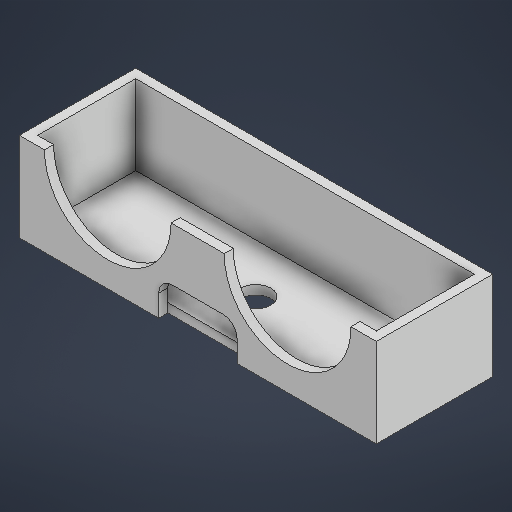
# Autodesk Inventor part: Ultrasonic Sensor Bracket Design
Saved by Autodesk Inventor 2027.1 (Build 311270010, 270A)
## iProperties
Created: 2026-10-28
Part Number: Ultrasonic Sensor Bracket Design
Material: Generic
Document SubType Name: Modeling
Designer: gaelo
Density: 1 g/cm^3
Appearance: Default
Author: gaelo
Autodesk Inventor part; units mm, degrees
ref_plane "YZ Plane" through (0, 0, 0) normal (1, 0, 0) x (0, 1, 0)
ref_plane "XZ Plane" through (0, 0, 0) normal (0, 1, 0) x (-1, 0, 0)
ref_plane "XY Plane" through (0, 0, 0) normal (0, 0, 1) x (1, 0, 0)
sketch "Sketch1" plane through (0, 0, 0) normal (0, 0, 1) x (1, 0, 0)
  line L0 (0, 0) -> (45.1, 0) construction
  line L1 (45.1, 0) -> (45.1, 10.21)
  line L2 (45.1, 10.21) -> (0, 10.21)
  line L3 (0, 10.21) -> (0, 0)
  line L4 (45.1, 0) -> (45.1, -1)
  line L5 (45.1, -1) -> (-0.0104, -1)
  line L6 (-0.0104, -1) -> (0, 0)
  dimension "d0" = 45.1
  dimension "d1" = 10.21
  dimension "d22" = 1
  dimension "d23" = 45.1104
  constraints: 14 end point, 2 parallel, 2 perpendicular, 1 horizontal, 1 vertical
  measures "d0" distance of L0.start L0.end
  measures "d1" distance of L0.end L1.end
  measures "d22" distance of L0.end L4.end
  measures "d23" distance of L4.end L5.end
extrude "Extrusion1" add sketch "Sketch1" against normal blind 14.7
shell "Shell1" thickness 1.15 removed faces 1 at (30.0667, 10.21, -4.9)
sketch "Sketch2" plane through (0, 0, 0) normal (0, 0, 1) x (1, 0, 0)
  line L0 (45.1, 10.21) -> (0, 10.21) construction
  line L1 (22.55, 10.21) -> (22.55, 0) construction
  line L2 (0, 0) -> (45.1, 0) construction
  line L3 (0, 0) -> (0, 10.21) construction
  line L4 (0, 5.105) -> (45.1, 5.105) construction
  line L5 (45.1, -1) -> (45.1, 10.21) construction
  line L6 (45.1, 10.21) -> (45.1, -1) construction
  line L7 (0, 10.21) -> (22.55, 0) construction
  line L8 (45.1, 10.21) -> (22.55, 0) construction
  circle A0 centre (33.825, 5.105) radius 8 construction
  circle A1 centre (11.275, 5.105) radius 8 construction
  line L9 (19.35, 1.75) -> (25.75, 1.75) construction
  line L10 (19.35, 0) -> (25.75, 0)
  line L11 (25.75, 3.5) -> (19.35, 3.5)
  arc A2 (19.35, 3.5) -> (19.35, 0) centre (19.35, 1.75) ccw
  arc A3 (25.75, 0) -> (25.75, 3.5) centre (25.75, 1.75) ccw
  line L12 (11.275, 5.105) -> (11.275, 10.21) construction
  line L13 (33.825, 5.105) -> (33.825, 10.21) construction
  circle A4 centre (11.1687, 10.1735) radius 8
  circle A5 centre (33.8884, 10.1153) radius 8
  line L14 (17.6, 1.75) -> (17.6, -1)
  line L15 (45.1, -1) -> (-0.0104, -1) projected
  line L16 (27.5, 1.75) -> (27.5, -1)
  point P0 (22.55, 1.75)
  dimension "d7" = 16
  dimension "d10" = 3.2
  dimension "d11" = 3.5
  dimension "d12" = 1.75
  dimension "d19" = 16
  dimension "d20" = 16
  constraints: 24 end point, 6 centre point, 6 midpoint, 6 point on circle, 6 point on line, 4 tangent, 3 parallel, 1 equal radius, 1 horizontal, 1 perpendicular, 1 vertical
  measures "d7" diameter of A1
  measures "d10" distance of point (22.55, 1.75) L9.end
  measures "d11" diameter of A3
  measures "d12" distance from line of L2 point (22.55, 1.75)
  measures "d19" diameter of A4
  measures "d20" diameter of A5
extrude "Extrusion2" cut sketch "Sketch2" against normal up to surface (1.15 mm away)
sketch "Sketch5" plane through (0, 0, 0) normal (0, 0, 1) x (1, 0, 0)
  arc A0 (19.35, 3.5) -> (17.6, 1.75) centre (19.35, 1.75) ccw projected
  line L0 (1.15, 0) -> (19.35, 0) projected
  line L1 (17.6, 1.75) -> (17.6, 0)
  arc A1 (27.5, 1.75) -> (25.75, 3.5) centre (25.75, 1.75) ccw projected
  line L2 (27.5, 1.75) -> (27.5, 0)
  line L3 (17.6, 0) -> (19.35, 0)
  arc A2 (17.6, 1.75) -> (19.35, 0) centre (19.35, 1.75) ccw
  arc A3 (25.75, 0) -> (27.5, 1.75) centre (25.75, 1.75) ccw
  line L4 (27.5, 0) -> (25.75, 0)
  point P0 (0, 0)
  point P1 (18.6411, 0.15)
  point P2 (26.4589, 0.15)
  point P3 (26.4589, 0.15)
  point P4 (18.6411, 0.15)
  constraints: 8 end point, 6 point on circle, 3 tangent, 2 centre point, 2 concentric, 2 horizontal, 1 perpendicular, 1 point on line, 1 vertical
extrude "Extrusion3" cut sketch "Sketch5" against normal up to surface (1.15 mm away)
sketch "Sketch7" plane through (1.15, 0.15, -13.55) normal (0, 1, 0) x (1, 0, 0)
  line L0 (-1.15, -13.55) -> (-1.15, 1.15) projected
  line L1 (-1.15, -6.2) -> (43.95, -6.2) construction
  line L2 (43.95, -13.55) -> (43.95, 1.15) projected
  line L3 (24.739, -12.4) -> (18.0186, -12.4) projected
  line L4 (21.3788, -12.4) -> (21.3788, 1.15) construction
  circle A0 centre (21.3788, -6.2) radius 1.8875
  dimension "d25" = 3.775
  constraints: 4 end point, 3 midpoint, 2 point on line, 1 centre point, 1 vertical
  measures "d25" diameter of A0
extrude "Extrusion4" cut sketch "Sketch7" against normal through all
body "Solid1"
